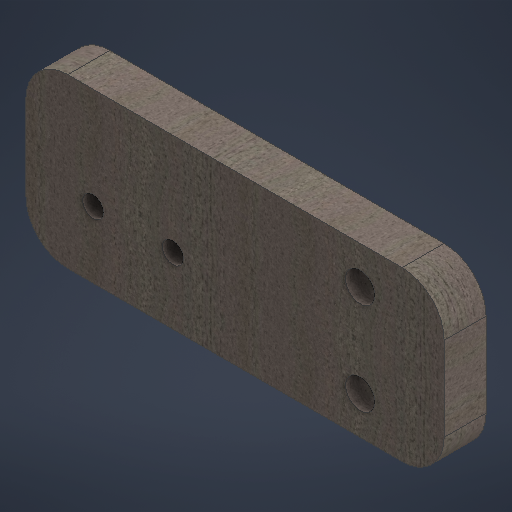
# Autodesk Inventor part: LimitSwitchMountPlate (X Axis)
Saved by Autodesk Inventor 2027.1 (Build 311270010, 270A)
## iProperties
Created: 2026-11-03
Part Number: LimitSwitchMountPlate (X Axis)
Material: Generic
Document SubType Name: Modeling
Designer: Ahmed
Density: 1 g/cm^3
Appearance: Walnut
Author: Ahmed
Autodesk Inventor part; units mm, degrees
ref_plane "YZ Plane" through (0, 0, 0) normal (1, 0, 0) x (0, 1, 0)
ref_plane "XZ Plane" through (0, 0, 0) normal (0, 1, 0) x (-1, 0, 0)
ref_plane "XY Plane" through (0, 0, 0) normal (0, 0, 1) x (1, 0, 0)
sketch "Sketch1" plane through (0, 0, 0) normal (0, 0, 1) x (1, 0, 0)
  line L0 (21.395, 10) -> (-18.395, 10)
  line L1 (-23.395, 5) -> (-23.395, -5)
  line L2 (-18.395, -10) -> (23.395, -10)
  circle A0 centre (-5.895, -2.1) radius 1.25
  circle A1 centre (-15.395, -2.1) radius 1.25
  arc A2 (-18.395, 10) -> (-23.395, 5) centre (-18.395, 5) ccw
  arc A3 (-23.395, -5) -> (-18.395, -10) centre (-18.395, -5) ccw
  circle A4 centre (16.395, -5.5) radius 1.75
  circle A5 centre (16.395, 5.5) radius 1.75
  line L3 (23.395, 0) -> (-23.395, 0) construction
  line L4 (26.395, -5) -> (26.395, 5)
  line L5 (21.395, 10) -> (23.395, 10)
  line L6 (23.395, -10) -> (21.395, -10)
  arc A6 (21.395, -10) -> (26.395, -5) centre (21.395, -5) ccw
  arc A7 (26.395, 5) -> (21.395, 10) centre (21.395, 5) ccw
  point P0 (0, 0)
  point P1 (3.395, 0)
  point P2 (-23.395, -10)
  point P3 (-23.395, 10)
  point P4 (3.395, -10)
  point P5 (0, 0)
  dimension "d0" = 46.79
  dimension "d1" = 20
  dimension "d2" = 2.5
  dimension "d3" = 2.5
  dimension "d4" = 9.5
  dimension "d5" = 7.9
  dimension "d6" = 8
  dimension "d7" = 5
  dimension "d8" = 3.5
  dimension "d9" = 3.5
  dimension "d10" = 4.5
  dimension "d11" = 3
  dimension "d12" = 49.79
  dimension "d13" = 23
  dimension "d14" = 3
  dimension "d15" = 10
  dimension "d16" = 5
  constraints: 14 end point, 8 centre point, 8 point on circle, 8 tangent, 5 point on line, 2 equal radius, 2 horizontal, 2 horizontal alignment, 2 midpoint, 2 vertical alignment, 1 coincident, 1 collinear, 1 parallel, 1 perpendicular, 1 symmetric about line, 1 vertical
  measures "d0" distance of L2.end point (-23.395, -10)
  measures "d1" distance of point (-23.395, 10) point (-23.395, -10)
  measures "d2" diameter of A0
  measures "d3" diameter of A1
  measures "d4" distance of A1.centre A0.centre
  measures "d5" distance from line of L2 A0.centre
  measures "d6" distance from line of L1 A1.centre
  measures "d7" radius of A2
  measures "d8" diameter of A4
  measures "d9" diameter of A5
  measures "d10" distance from line of L2 A4.centre
  measures "d11" distance from line of L5.end L4
  measures "d12" distance between parallel lines of L4 L1
  measures "d13" distance from line of point (3.395, 0) L4
  measures "d14" distance from line of L3.start L4
  measures "d15" distance from line of A5.centre L4
  measures "d16" radius of A6
extrude "Extrusion1" add sketch "Sketch1" along normal blind 5
body "Solid1"
